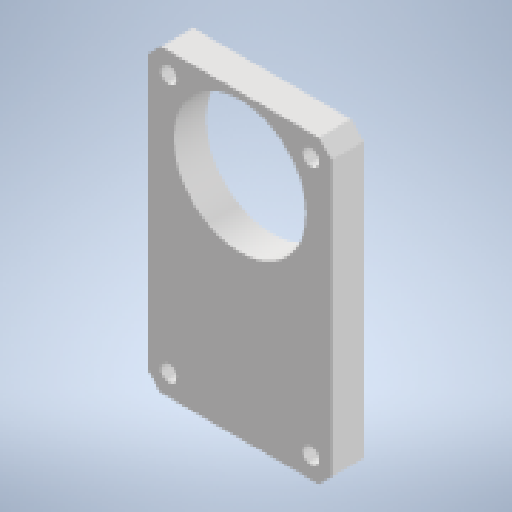
# Autodesk Inventor part: ConnectortoElbowBot
Saved by Autodesk Inventor 2025.2 (Build 292293000, 293)
## iProperties
Created: 2025-06-27
Part Number: ConnectortoElbowBot
Material: Generic
Document SubType Name: Modeling
Designer: ricoa
Density: 1 g/cm^3
Appearance: Default
Author: ricoa
Autodesk Inventor part; units mm, degrees
ref_plane "YZ Plane" through (0, 0, 0) normal (1, 0, 0) x (0, 1, 0)
ref_plane "XZ Plane" through (0, 0, 0) normal (0, 1, 0) x (-1, 0, 0)
ref_plane "XY Plane" through (0, 0, 0) normal (0, 0, 1) x (1, 0, 0)
sketch "Sketch1" plane through (0, 0, 0) normal (0, 0, 1) x (1, 0, 0)
  line L0 (28.5, 44.5) -> (28.5, 27) projected
  line L1 (28.5, 44.5) -> (28.5, 2) projected
  line L2 (28.5, 2) -> (26.5, 0) projected
  line L3 (26.5, 0) -> (2, 0) projected
  line L4 (2, 0) -> (0, 2) projected
  line L5 (0, 2) -> (0, 14.5) projected
  line L6 (0, 44.5) -> (2, 46.5) projected
  line L7 (0, 27) -> (0, 44.5) projected
  line L8 (0, 44.5) -> (0, 2) projected
  line L9 (2, 46.5) -> (10.25, 46.5) projected
  line L10 (10.25, 46.5) -> (18.25, 46.5) projected
  line L11 (18.25, 46.5) -> (26.5, 46.5) projected
  line L12 (26.5, 46.5) -> (28.5, 44.5) projected
  circle A0 centre (14.25, 35.25) radius 9.75 projected
  circle A1 centre (25.25, 43.25) radius 1.25
  circle A2 centre (3.25, 43.25) radius 1.25
  circle A3 centre (25.25, 3.25) radius 1.25
  circle A4 centre (3.25, 3.25) radius 1.25
  circle A5 centre (14.25, 35.25) radius 10.25
  dimension "d0" = 2.5
  dimension "d1" = 2.5
  dimension "d2" = 2.5
  dimension "d3" = 2.5
  dimension "d4" = 0.5
  constraints: 5 centre point
  measures "d0" diameter of A1
  measures "d1" diameter of A2
  measures "d2" diameter of A3
  measures "d3" diameter of A4
  measures "d4" radial gap between concentric circles of A0 A5
extrude "Extrusion1" add sketch "Sketch1" along normal blind 5 contours L0 L1 L2 L3 L4 L5 L8 L7 L6 L9 L10 L11 L12
body "Solid1"
